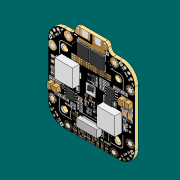
# Autodesk Inventor part: MatekFChub12S
Saved by Autodesk Inventor 2021.2 (Build 252289000, 289)
## iProperties
Created: 2022-09-25
Part Number: MatekFChub12S
Material: Generic
Document SubType Name: Modeling
Designer: Medvezh0n0k
Density: 1 g/cm^3
Appearance: Default
Author: Medvezh0n0k
Autodesk Inventor part; units mm, degrees
sketch "Sketch1" plane through (0, 0, 0) normal (0, 0, 1) x (1, 0, 0)
  line L0 (25, -25) -> (-25, -25)
  line L1 (-25, -25) -> (-25, 25)
  line L2 (-25, 25) -> (25, 25)
  line L3 (25, 25) -> (25, -25)
  line L4 (25, -25) -> (-25, 25) construction
  line L5 (-25, -25) -> (25, 25) construction
  line L6 (-9.5, 30) -> (9.5, 30)
  line L7 (9.5, 30) -> (9.5, 25)
  line L8 (9.5, 25) -> (-9.5, 25)
  line L9 (-9.5, 25) -> (-9.5, 30)
  line L10 (15.25, -15.25) -> (-15.25, -15.25) construction
  line L11 (-15.25, -15.25) -> (-15.25, 15.25) construction
  line L12 (-15.25, 15.25) -> (15.25, 15.25) construction
  line L13 (15.25, 15.25) -> (15.25, -15.25) construction
  line L14 (15.25, -15.25) -> (-15.25, 15.25) construction
  line L15 (-15.25, -15.25) -> (15.25, 15.25) construction
  circle A0 centre (15.25, 15.25) radius 1.6
  circle A1 centre (15.25, -15.25) radius 1.6
  circle A2 centre (-15.25, -15.25) radius 1.6
  circle A3 centre (-15.25, 15.25) radius 1.6
  point P0 (0, 0)
  point P1 (0, 25)
  dimension "d0" = 50
  dimension "d1" = 30.5
  dimension "d2" = 5
  dimension "d3" = 19
  dimension "d4" = 3.2
  constraints: 32 end point, 6 midpoint, 6 parallel, 5 perpendicular, 4 centre point, 4 coincident, 3 equal radius, 3 horizontal
  measures "d0" distance of L0.start L0.end
  measures "d1" distance of L11.end L12.end
  measures "d2" distance of L6.end L7.end
  measures "d3" distance of L6.start L6.end
  measures "d4" diameter of A0
extrude "Extrusion1" add sketch "Sketch1" along normal blind 2
fillet "Fillet1" radius 9 4 edges at (-25, 25, 1) (25, 25, 1) (25, -25, 1) (-25, -25, 1)
fillet "Fillet1" radius 2 2 edges at (-9.5, 30, 1) (9.5, 30, 1)
fillet "Fillet1" radius 3 2 edges at (-9.5, 25, 1) (9.5, 25, 1)
sketch "Sketch2" plane through (0, 0, 2) normal (0, 0, 1) x (1, 0, 0)
  line L0 (6.9321, -0.4285) -> (17.3962, -0.4285)
  line L1 (17.3962, -0.4285) -> (17.3962, -10.8927)
  line L2 (17.3962, -10.8927) -> (6.9321, -10.8927)
  line L3 (6.9321, -10.8927) -> (6.9321, -0.4285)
  line L4 (-17.5369, 11.4564) -> (-7.0728, 11.4564)
  line L5 (-7.0728, 11.4564) -> (-7.0728, 0.9923)
  line L6 (-7.0728, 0.9923) -> (-17.5369, 0.9923)
  line L7 (-17.5369, 0.9923) -> (-17.5369, 11.4564)
  line L8 (-7.5915, 22.4844) -> (-0.6003, 22.4844)
  line L9 (-0.6003, 22.4844) -> (-0.6003, 15.809)
  line L10 (-0.6003, 15.809) -> (-7.5915, 15.809)
  line L11 (-7.5915, 15.809) -> (-7.5915, 22.4844)
  line L12 (0.5724, 22.4844) -> (7.5635, 22.4844)
  line L13 (7.5635, 22.4844) -> (7.5635, 15.6285)
  line L14 (7.5635, 15.6285) -> (0.5724, 15.6285)
  line L15 (0.5724, 15.6285) -> (0.5724, 22.4844)
  line L16 (-6.5309, -14.0469) -> (5.4691, -14.0469)
  line L17 (5.4691, -14.0469) -> (5.4691, -18.3769)
  line L18 (5.4691, -18.3769) -> (-6.5309, -18.3769)
  line L19 (-6.5309, -18.3769) -> (-6.5309, -14.0469)
  line L20 (-14.0188, -3.8564) -> (-9.779, -3.8564)
  line L21 (-9.779, -3.8564) -> (-9.779, -8.2766)
  line L22 (-9.779, -8.2766) -> (-14.0188, -8.2766)
  line L23 (-14.0188, -8.2766) -> (-14.0188, -3.8564)
  line L24 (9.706, 8.7727) -> (13.4947, 8.7727)
  line L25 (13.4947, 8.7727) -> (13.4947, 3.9015)
  line L26 (13.4947, 3.9015) -> (9.706, 3.9015)
  line L27 (9.706, 3.9015) -> (9.706, 8.7727)
  line L28 (8.443, 3.27) -> (12.5926, 3.27)
  line L29 (12.5926, 3.27) -> (12.5926, 0.2029)
  line L30 (12.5926, 0.2029) -> (8.443, 0.2029)
  line L31 (8.443, 0.2029) -> (8.443, 3.27)
  line L32 (-1.3896, 3.9917) -> (1.497, 3.9917)
  line L33 (1.497, 3.9917) -> (1.497, 2.0071)
  line L34 (1.497, 2.0071) -> (-1.3896, 2.0071)
  line L35 (-1.3896, 2.0071) -> (-1.3896, 3.9917)
  line L36 (0.5949, 10.1258) -> (2.3089, 10.1258)
  line L37 (2.3089, 10.1258) -> (2.3089, 7.5098)
  line L38 (2.3089, 7.5098) -> (0.5949, 7.5098)
  line L39 (0.5949, 7.5098) -> (0.5949, 10.1258)
  line L40 (5.7368, -12.2232) -> (8.7137, -12.2232)
  line L41 (8.7137, -12.2232) -> (8.7137, -13.9372)
  line L42 (8.7137, -13.9372) -> (5.7368, -13.9372)
  line L43 (5.7368, -13.9372) -> (5.7368, -12.2232)
  line L44 (9.2549, -12.2683) -> (12.2318, -12.2683)
  line L45 (12.2318, -12.2683) -> (12.2318, -13.9823)
  line L46 (12.2318, -13.9823) -> (9.2549, -13.9823)
  line L47 (9.2549, -13.9823) -> (9.2549, -12.2683)
  line L48 (-23.5809, -4.4879) -> (-21.5061, -4.4879)
  line L49 (-21.5061, -4.4879) -> (-21.5061, -7.6452)
  line L50 (-21.5061, -7.6452) -> (-23.5809, -7.6452)
  line L51 (-23.5809, -7.6452) -> (-23.5809, -4.4879)
  line L52 (-20.604, -4.6683) -> (-18.0782, -4.6683)
  line L53 (-18.0782, -4.6683) -> (-18.0782, -7.4648)
  line L54 (-18.0782, -7.4648) -> (-20.604, -7.4648)
  line L55 (-20.604, -7.4648) -> (-20.604, -4.6683)
  line L56 (17.6443, 7.8706) -> (20.1701, 7.8706)
  line L57 (20.1701, 7.8706) -> (20.1701, 4.6231)
  line L58 (20.1701, 4.6231) -> (17.6443, 4.6231)
  line L59 (17.6443, 4.6231) -> (17.6443, 7.8706)
  line L60 (21.3428, 7.8706) -> (23.8687, 7.8706)
  line L61 (23.8687, 7.8706) -> (23.8687, 5.0742)
  line L62 (23.8687, 5.0742) -> (21.3428, 5.0742)
  line L63 (21.3428, 5.0742) -> (21.3428, 7.8706)
  point P0 (0, 0)
  dimension "d42" = 4.33
  dimension "d43" = 12
  constraints: 128 end point, 32 parallel, 16 horizontal, 16 perpendicular, 10 equal length
  measures "d42" distance of L18.end L16.start
  measures "d43" distance of L16.start L16.end
extrude "Extrusion2" add sketch "Sketch2" along normal blind 6 from surface at -2 contours L0 L1 L2 L3 | L4 L5 L6 L7
extrude "Extrusion3" add sketch "Sketch2" along normal blind 1 contours L8 L9 L10 L11 | L12 L13 L14 L15
extrude "Extrusion4" add sketch "Sketch2" along normal blind 2.5 contours L16 L17 L18 L19
extrude "Extrusion5" add sketch "Sketch2" along normal blind 2.5 contours L48 L49 L50 L51 | L52 L53 L54 L55 | L56 L57 L58 L59 | L60 L61 L62 L63
extrude "Extrusion6" add sketch "Sketch2" along normal blind 1 contours L20 L21 L22 L23 | L24 L25 L26 L27 | L28 L29 L30 L31 | L32 L33 L34 L35 | L36 L37 L38 L39 | L40 L41 L42 L43 | L44 L45 L46 L47
sketch "Sketch3" plane through (0, 0, 2) normal (0, 0, 1) x (1, 0, 0)
  line L0 (-16, -25) -> (16, -25) construction
  line L1 (-25, 16) -> (-25, -16) construction
  line L2 (-85.3032, 30.8316) -> (25.6981, 30.8316) construction
  line L3 (25.6981, 30.8316) -> (25.6981, -26.2225) construction
  line L4 (25.6981, -26.2225) -> (-85.3032, -26.2225) construction
  line L5 (-85.3032, -26.2225) -> (-85.3032, 30.8316) construction
  point P0 (0, 0)
  constraints: 1 horizontal, 2 other
decal "Decal1"
sketch "Sketch4" plane through (0, 0, 0) normal (0, 0, -1) x (-1, 0, 0)
  line L0 (-25.6537, 30.1199) -> (83.0731, 30.1199) construction
  line L1 (83.0731, 30.1199) -> (83.0731, -25.7651) construction
  line L2 (83.0731, -25.7651) -> (-25.6537, -25.7651) construction
  line L3 (-25.6537, -25.7651) -> (-25.6537, 30.1199) construction
  point P0 (0, 0)
  constraints: 1 vertical, 2 other
decal "Decal2"
body "Solid1"
